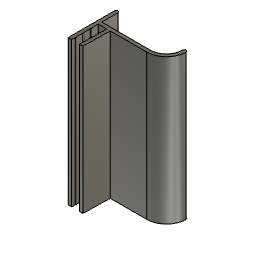
Glass Board Pen Holder v5 (Autodesk Fusion 360 design; units mm, degrees)
Autodesk Fusion 360 part; units mm, degrees
sketch "Sketch1" plane through (0, 0, 0) normal (0, 0, 1) x (1, 0, 0)
  line L0 (0, 0) -> (37, 0) construction
  line L1 (37, 0) -> (37, -20) construction
  line L2 (37, -20) -> (0, -20) construction
  line L3 (0, -20) -> (0, 0) construction
  line L4 (0, -20) -> (37, -20) construction
  line L5 (37, -20) -> (37, -4.4) construction
  line L6 (37, -4.4) -> (0, -4.4) construction
  line L7 (0, -4.4) -> (0, -20) construction
  line L8 (0, -4.4) -> (37, -4.4) construction
  line L9 (37, -4.4) -> (37, -6.15) construction
  line L10 (37, -6.15) -> (0, -6.15) construction
  line L11 (0, -6.15) -> (0, -4.4) construction
  line L12 (0, -6.15) -> (1.75, -6.15) construction
  line L13 (1.75, -6.15) -> (1.75, -20) construction
  line L14 (1.75, -20) -> (0, -20) construction
  line L15 (0, -20) -> (0, -6.15) construction
  line L16 (6.15, -6.15) -> (5.9, -20) construction
  line L17 (7.9003, -6.15) -> (7.6503, -20) construction
  circle A0 centre (1.75, -10.05) radius 0.3 construction
  circle A1 centre (1.75, -13.95) radius 0.3 construction
  circle A2 centre (1.75, -17.85) radius 0.3 construction
  circle A3 centre (6.0796, -10.05) radius 0.3 construction
  circle A4 centre (6.0092, -13.95) radius 0.3 construction
  circle A5 centre (5.9388, -17.85) radius 0.3 construction
  line L18 (0, 0) -> (37, 0) construction
  line L19 (37, 0) -> (37, 4) construction
  line L20 (37, 4) -> (0, 4) construction
  line L21 (0, 4) -> (0, 0) construction
  arc A6 (26.85, -6.15) -> (37, 4) centre (26.85, 4) ccw
  arc A7 (26.85, -4.4) -> (35.25, 4) centre (26.85, 4) ccw
  circle A8 centre (36.125, 4) radius 0.875 construction
  line L22 (1.75, -6.15) -> (0, -6.15) construction
  line L23 (0, -6.15) -> (0, 4) construction
  line L24 (0, 4) -> (1.75, 4) construction
  line L25 (1.75, 4) -> (1.75, -6.15) construction
  circle A9 centre (0.875, 4) radius 0.875 construction
  line L26 (0, 0) -> (0, -20)
  line L27 (0, -20) -> (1.75, -20)
  line L28 (1.75, -20) -> (1.75, -18.15)
  line L29 (1.75, -17.55) -> (1.75, -14.25)
  line L30 (1.75, -13.65) -> (1.75, -10.35)
  line L31 (1.75, -9.75) -> (1.75, -6.15)
  line L32 (1.75, -6.15) -> (6.15, -6.15)
  line L33 (6.15, -6.15) -> (6.085, -9.75)
  line L34 (6.0742, -10.35) -> (6.0146, -13.65)
  line L35 (6.0038, -14.25) -> (5.9442, -17.55)
  line L36 (5.9334, -18.15) -> (5.9, -20)
  line L37 (5.9, -20) -> (7.6503, -20)
  line L38 (7.6503, -20) -> (7.9003, -6.15)
  line L39 (7.9003, -6.15) -> (26.85, -6.15)
  line L40 (26.85, -4.4) -> (1.75, -4.4)
  line L41 (1.75, -4.4) -> (1.75, 4)
  line L42 (0, 4) -> (0, 0)
  arc A10 (1.75, -18.15) -> (1.75, -17.55) centre (1.75, -17.85) ccw
  arc A11 (1.75, -14.25) -> (1.75, -13.65) centre (1.75, -13.95) ccw
  arc A12 (1.75, -10.35) -> (1.75, -9.75) centre (1.75, -10.05) ccw
  arc A13 (6.085, -9.75) -> (6.0742, -10.35) centre (6.0796, -10.05) ccw
  arc A14 (6.0146, -13.65) -> (6.0038, -14.25) centre (6.0092, -13.95) ccw
  arc A15 (5.9442, -17.55) -> (5.9334, -18.15) centre (5.9388, -17.85) ccw
  arc A16 (1.75, 4) -> (0, 4) centre (0.875, 4) ccw
  arc A17 (37, 4) -> (35.25, 4) centre (36.125, 4) ccw
  dimension "d1" = 37
  dimension "d2" = 20
  dimension "d3" = 15.6
  dimension "d4" = 1.75
  dimension "d5" = 1.75
  dimension "d7" = 4.4
  dimension "d8" = 4.15
  dimension "d9" = 1.75
  dimension "d10" = 3.9
  dimension "d11" = 7.8
  dimension "d12" = 11.7
  dimension "d13" = 3.9
  dimension "d14" = 7.8
  dimension "d15" = 11.7
  dimension "d16" = 0.6
  dimension "d17" = 0.6
  dimension "d18" = 0.6
  dimension "d19" = 4
  constraint horizontal L0
  constraint vertical L1
  constraint horizontal L2
  constraint vertical L3
  constraint coincident L0.start L3.end
  constraint horizontal L4
  constraint vertical L5
  constraint horizontal L6
  constraint vertical L7
  constraint collinear L1 L5
  constraint horizontal L8
  constraint vertical L9
  constraint horizontal L10
  constraint vertical L11
  constraint collinear L5 L9
  constraint horizontal L12
  constraint vertical L13
  constraint horizontal L14
  constraint vertical L15
  constraint collinear L2 L14
  constraint coincident L10 L16.start
  constraint coincident L2 L16.end
  constraint coincident L10 L17.start
  constraint coincident L4 L17.end
  constraint parallel L16 L17
  constraint coincident L13 A0.centre
  constraint coincident L13 A1.centre
  constraint coincident L13 A2.centre
  constraint coincident L16 A3.centre
  constraint coincident L16 A4.centre
  constraint coincident L16 A5.centre
  constraint equal A0 A3
  constraint equal A1 A4
  constraint equal A2 A5
  constraint horizontal L18
  constraint vertical L19
  constraint horizontal L20
  constraint vertical L21
  constraint collinear L1 L19
  constraint tangent L10 A6
  constraint coincident L10 A6.start
  constraint coincident L20 A6.centre
  constraint coincident L19.end A8
  constraint tangent A6 A8
  constraint coincident A7.end A8
  constraint horizontal L22
  constraint vertical L23
  constraint horizontal L24
  constraint vertical L25
  constraint coincident L24.end A9
  constraint tangent L25 A9
  constraint coincident L20.end A9
  constraint coincident A2 L28.end
  constraint coincident L13 L28.end
  constraint coincident A2 L29.start
  constraint coincident L13 L29.start
  constraint coincident L13 L29.end
  constraint coincident A1 L29.end
  constraint coincident L13 L30.start
  constraint coincident A1 L30.start
  constraint coincident L13 L30.end
  constraint coincident A0 L30.end
  constraint coincident L13 L31.start
  constraint coincident A0 L31.start
  constraint coincident A3 L33.end
  constraint coincident L16 L33.end
  constraint coincident L16 L34.start
  constraint coincident A3 L34.start
  constraint coincident A4 L34.end
  constraint coincident L16 L34.end
  constraint coincident A4 L35.start
  constraint coincident L16 L35.start
  constraint coincident A5 L35.end
  constraint coincident L16 L35.end
  constraint coincident A5 L36.start
  constraint coincident L16 L36.start
  constraint coincident L8 L40.end
  constraint coincident L25 L40.end
  constraint tangent A7 L40
  constraint coincident A2.centre A10.centre
  constraint coincident A1.centre A11.centre
  constraint coincident A0.centre A12.centre
  constraint coincident A3.centre A13.centre
  constraint coincident A4.centre A14.centre
  constraint coincident A5.centre A15.centre
  constraint coincident A9.centre A16.centre
  constraint coincident A8.centre A17.centre
  measures "d1" distance of L0.start L0.end
  measures "d2" distance of L0.start L2.end
  measures "d3" distance of L2.end L6.end
  measures "d4" distance of L6.end L10.end
  measures "d5" distance of L10.end L12.end
  measures "d7" distance of L12.end L16.start
  measures "d8" distance of L13.end L16.end
  measures "d9" distance of L16 L17
  measures "d10" distance of L10 A0.centre
  measures "d11" distance of L10 A1.centre
  measures "d12" distance of L10 A2.centre
  measures "d13" distance of L10 A3.centre
  measures "d14" distance of L10 A4.centre
  measures "d15" distance of L10 A5.centre
  measures "d16" diameter of A2
  measures "d17" diameter of A1
  measures "d18" diameter of A0
  measures "d19" distance of L0.start L20.end
extrude "Extrude1" add sketch "Sketch1" along normal blind 75
equation "d1 = 33.5 mm + ( 1.75 * 2 ) * 1 mm"
equation "d5 = thickness"
equation "thickness = 1.75 mm"
equation "d9 = thickness"
equation "d10 = d3 / 4"
equation "d11 = d3 / 4 * 2"
equation "d12 = d3 / 4 * 3"
equation "d13 = d10"
equation "d14 = d11"
equation "d15 = d12"
equation "d17 = d16"
equation "d18 = d16"
equation "d20 = -thickness"
